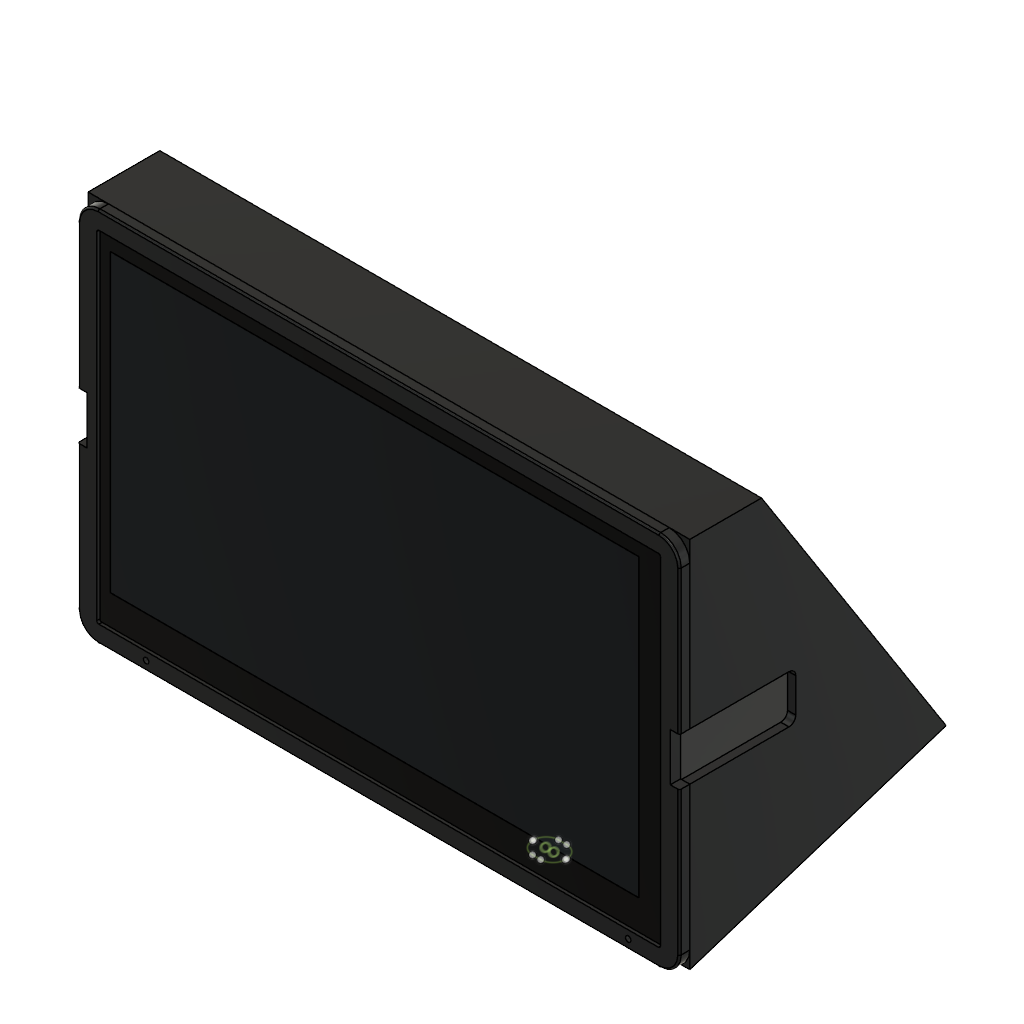
03-NP2 - Mesa V03 - sem base - audio traseiro (Autodesk Fusion 360 design; units mm, degrees)
Autodesk Fusion 360 part; units mm, degrees
sketch "Esboço1" plane through (0, 0, 0) normal (0, 0, 1) x (1, 0, 0) in component "01 / Moldura fina / microfones frontais"
  line L0 (-82, -55) -> (82, -55)
  line L1 (88, -49) -> (88, 49)
  line L2 (82, 55) -> (-82, 55)
  line L3 (-88, 49) -> (-88, -49)
  arc A0 (82, -55) -> (88, -49) centre (82, -49) ccw
  arc A1 (88, 49) -> (82, 55) centre (82, 49) ccw
  arc A2 (-82, 55) -> (-88, 49) centre (-82, 49) ccw
  arc A3 (-88, -49) -> (-82, -55) centre (-82, -49) ccw
extrude "Frente 176 x 110 R6" add sketch "Esboço1" against normal blind 3 makes body 1 in component "01 / Moldura fina / microfones frontais"
fillet "Borda de toque suave" radius 0.5 64 edges at (0, -55, 0) (86.2426, -53.2426, 0) (88, 0, 0) (86.2426, 53.2426, 0) (0, 55, 0) (-86.2426, 53.2426, 0) (-88, 0, 0) (-86.2426, -53.2426, 0) (86.2426, -53.2426, 0) (88, 0, 0) (86.2426, 53.2426, 0) (0, 55, 0) (-86.2426, 53.2426, 0) (-88, 0, 0) (-86.2426, -53.2426, 0) (0, -55, 0) (88, 0, 0) (86.2426, 53.2426, 0) (0, 55, 0) (-86.2426, 53.2426, 0) (-88, 0, 0) (-86.2426, -53.2426, 0) (0, -55, 0) (86.2426, -53.2426, 0) (86.2426, 53.2426, 0) (0, 55, 0) (-86.2426, 53.2426, 0) (-88, 0, 0) (-86.2426, -53.2426, 0) (0, -55, 0) (86.2426, -53.2426, 0) (88, 0, 0) (0, 55, 0) (-86.2426, 53.2426, 0) (-88, 0, 0) (-86.2426, -53.2426, 0) (0, -55, 0) (86.2426, -53.2426, 0) (88, 0, 0) (86.2426, 53.2426, 0) (-86.2426, 53.2426, 0) (-88, 0, 0) (-86.2426, -53.2426, 0) (0, -55, 0) (86.2426, -53.2426, 0) (88, 0, 0) (86.2426, 53.2426, 0) (0, 55, 0) (-88, 0, 0) (-86.2426, -53.2426, 0) (0, -55, 0) (86.2426, -53.2426, 0) (88, 0, 0) (86.2426, 53.2426, 0) (0, 55, 0) (-86.2426, 53.2426, 0) (-86.2426, -53.2426, 0) (0, -55, 0) (86.2426, -53.2426, 0) (88, 0, 0) (86.2426, 53.2426, 0) (0, 55, 0) (-86.2426, 53.2426, 0) (-88, 0, 0) on bodies 1 in component "01 / Moldura fina / microfones frontais"
ref_plane "Plano de trabalho1" through (0, 0, 0.1) normal (0, 0, 1) x (1, 0, 0) in component "01 / Moldura fina / microfones frontais"
sketch "Esboço2" plane through (0, 0, 0.1) normal (0, 0, 1) x (1, 0, 0) in component "01 / Moldura fina / microfones frontais"
  line L0 (-81.84, -49.885) -> (81.84, -49.885)
  line L1 (82.44, -49.285) -> (82.44, 49.285)
  line L2 (81.84, 49.885) -> (-81.84, 49.885)
  line L3 (-82.44, 49.285) -> (-82.44, -49.285)
  arc A0 (81.84, -49.885) -> (82.44, -49.285) centre (81.84, -49.285) ccw
  arc A1 (82.44, 49.285) -> (81.84, 49.885) centre (81.84, 49.285) ccw
  arc A2 (-81.84, 49.885) -> (-82.44, 49.285) centre (-81.84, 49.285) ccw
  arc A3 (-82.44, -49.285) -> (-81.84, -49.885) centre (-81.84, -49.285) ccw
extrude "Janela vidro / folga 0.3 mm por lado" cut sketch "Esboço2" against normal blind 3.3 bodies 1 in component "01 / Moldura fina / microfones frontais"
ref_plane "Plano de trabalho2" through (0, 0, 0.1) normal (0, 0, 1) x (1, 0, 0) in component "01 / Moldura fina / microfones frontais"
sketch "Esboço3" plane through (0, 0, 0.1) normal (0, 0, 1) x (1, 0, 0) in component "01 / Moldura fina / microfones frontais"
  circle A0 centre (-68, -52.2) radius 0.8
  circle A1 centre (73, -52.2) radius 0.8
extrude "MIC 1 e MIC 2 / borda inferior" cut sketch "Esboço3" against normal blind 3.3 bodies 1 in component "01 / Moldura fina / microfones frontais"
ref_plane "Plano de trabalho1" through (0, 0, -0.65) normal (0, 0, 1) x (1, 0, 0) in component "REF / Vidro 164.28 x 99.17 / area ativa assimetrica"
sketch "Esboço1 (2)" plane through (0, 0, -0.65) normal (0, 0, 1) x (1, 0, 0) in component "REF / Vidro 164.28 x 99.17 / area ativa assimetrica"
  line L0 (-81.89, -49.585) -> (81.89, -49.585)
  line L1 (82.14, -49.335) -> (82.14, 49.335)
  line L2 (81.89, 49.585) -> (-81.89, 49.585)
  line L3 (-82.14, 49.335) -> (-82.14, -49.335)
  arc A0 (81.89, -49.585) -> (82.14, -49.335) centre (81.89, -49.335) ccw
  arc A1 (82.14, 49.335) -> (81.89, 49.585) centre (81.89, 49.335) ccw
  arc A2 (-81.89, 49.585) -> (-82.14, 49.335) centre (-81.89, 49.335) ccw
  arc A3 (-82.14, -49.335) -> (-81.89, -49.585) centre (-81.89, -49.335) ccw
extrude "Vidro do display" add sketch "Esboço1 (2)" against normal blind 2.15 separate body makes body 2 in component "REF / Vidro 164.28 x 99.17 / area ativa assimetrica"
ref_plane "Plano de trabalho2" through (0, 0, -0.6) normal (0, 0, 1) x (1, 0, 0) in component "REF / Vidro 164.28 x 99.17 / area ativa assimetrica"
sketch "Esboço2 (2)" plane through (0, 0, -0.6) normal (0, 0, 1) x (1, 0, 0) in component "REF / Vidro 164.28 x 99.17 / area ativa assimetrica"
  line L0 (-78.985, -40.855) -> (75.395, -40.855)
  line L1 (75.495, -40.755) -> (75.495, 45.465)
  line L2 (75.395, 45.565) -> (-78.985, 45.565)
  line L3 (-79.085, 45.465) -> (-79.085, -40.755)
  arc A0 (75.395, -40.855) -> (75.495, -40.755) centre (75.395, -40.755) ccw
  arc A1 (75.495, 45.465) -> (75.395, 45.565) centre (75.395, 45.465) ccw
  arc A2 (-78.985, 45.565) -> (-79.085, 45.465) centre (-78.985, 45.465) ccw
  arc A3 (-79.085, -40.755) -> (-78.985, -40.855) centre (-78.985, -40.755) ccw
extrude "Area ativa 154.58 x 86.42" add sketch "Esboço2 (2)" against normal blind 0.04 separate body makes body 3 in component "REF / Vidro 164.28 x 99.17 / area ativa assimetrica"
ref_plane "Plano de trabalho1" through (-88, 0, 0) normal (1, 0, 0) x (0, 1, 0) in component "02 / Corpo em cunha / apoio direto na mesa"
sketch "Esboço1 (3)" plane through (-88, 0, 0) normal (1, 0, 0) x (0, 0, -1) in component "02 / Corpo em cunha / apoio direto na mesa"
  line L0 (3, -54) -> (3, 55)
  line L1 (3, 55) -> (24, 55)
  line L2 (24, 55) -> (78, -29.6563)
  line L3 (78, -29.6563) -> (3, -54)
extrude "Volume externo da cunha" add sketch "Esboço1 (3)" along normal blind 176 separate body makes body 4 in component "02 / Corpo em cunha / apoio direto na mesa"
shell "Paredes 2.4 / frente e traseira abertas" thickness 2.4 removed faces 2 at (-29.3333, -17.6667, -3) at (-29.3333, 26.7812, -42) on bodies 4 in component "02 / Corpo em cunha / apoio direto na mesa"
ref_plane "Plano de trabalho2" through (-88.1, 0, 0) normal (1, 0, 0) x (0, 1, 0) in component "02 / Corpo em cunha / apoio direto na mesa"
sketch "Esboço2 (3)" plane through (-88.1, 0, 0) normal (1, 0, 0) x (0, 0, -1) in component "02 / Corpo em cunha / apoio direto na mesa"
  line L0 (-2, -7) -> (32, -7)
  line L1 (34, -5) -> (34, 5)
  line L2 (32, 7) -> (-2, 7)
  line L3 (-4, 5) -> (-4, -5)
  arc A0 (32, -7) -> (34, -5) centre (32, -5) ccw
  arc A1 (34, 5) -> (32, 7) centre (32, 5) ccw
  arc A2 (-2, 7) -> (-4, 5) centre (-2, 5) ccw
  arc A3 (-4, -5) -> (-2, -7) centre (-2, -5) ccw
extrude "Acesso lateral / USB e expansao" cut sketch "Esboço2 (3)" along normal blind 2.8 bodies 1 in component "01 / Moldura fina / microfones frontais"
extrude "Extrusão2" cut sketch "Esboço2 (3)" along normal blind 2.8 bodies 4 in component "02 / Corpo em cunha / apoio direto na mesa"
ref_plane "Plano de trabalho3" through (88.1, 0, 0) normal (1, 0, 0) x (0, 1, 0) in component "02 / Corpo em cunha / apoio direto na mesa"
sketch "Esboço3 (2)" plane through (88.1, 0, 0) normal (1, 0, 0) x (0, 0, -1) in component "02 / Corpo em cunha / apoio direto na mesa"
  line L0 (-2, -7) -> (32, -7)
  line L1 (34, -5) -> (34, 5)
  line L2 (32, 7) -> (-2, 7)
  line L3 (-4, 5) -> (-4, -5)
  arc A0 (32, -7) -> (34, -5) centre (32, -5) ccw
  arc A1 (34, 5) -> (32, 7) centre (32, 5) ccw
  arc A2 (-2, 7) -> (-4, 5) centre (-2, 5) ccw
  arc A3 (-4, -5) -> (-2, -7) centre (-2, -5) ccw
extrude "Acesso lateral / USB e expansao (1)" cut sketch "Esboço3 (2)" against normal blind 2.8 bodies 1 in component "01 / Moldura fina / microfones frontais"
extrude "Extrusão3" cut sketch "Esboço3 (2)" against normal blind 2.8 bodies 4 in component "02 / Corpo em cunha / apoio direto na mesa"
ref_plane "Plano de trabalho4" through (0, -55.1, 0) normal (0, 1, 0) x (0, 0, 1) in component "02 / Corpo em cunha / apoio direto na mesa"
sketch "Esboço4" plane through (0, -55.1, 0) normal (0, 1, 0) x (1, 0, 0) in component "02 / Corpo em cunha / apoio direto na mesa"
  line L0 (34.8, 10.2) -> (37.2, 10.2)
  line L1 (40.8, 13.8) -> (40.8, 14.2)
  line L2 (37.2, 17.8) -> (34.8, 17.8)
  line L3 (31.2, 14.2) -> (31.2, 13.8)
  arc A0 (37.2, 10.2) -> (40.8, 13.8) centre (37.2, 13.8) ccw
  arc A1 (40.8, 14.2) -> (37.2, 17.8) centre (37.2, 14.2) ccw
  arc A2 (34.8, 17.8) -> (31.2, 14.2) centre (34.8, 14.2) ccw
  arc A3 (31.2, 13.8) -> (34.8, 10.2) centre (34.8, 13.8) ccw
component "01 / Moldura fina / microfones frontais" placed x (1, 0, 0) y (0, 1, 0) z (0, 0, 1) at (0, 0, 0)
component "REF / Vidro 164.28 x 99.17 / area ativa assimetrica" placed x (1, 0, 0) y (0, 1, 0) z (0, 0, 1) at (0, 0, 0)
component "02 / Corpo em cunha / apoio direto na mesa" placed x (1, 0, 0) y (0, 1, 0) z (0, 0, 1) at (0, 0, 0)
equation "wall = 2.4 mm" comment "Parede da carcaca"
equation "bezel = 3 mm" comment "Moldura frontal"
equation "rear_cover = 2.4 mm" comment "Tampa traseira"
equation "pcb_holes_x = 156 mm" comment "Entre furos da foto"
equation "pcb_holes_y = 89 mm" comment "Entre furos; PCB total 97 mm"
equation "d6 = -bezel"
equation "d30 = wall"
